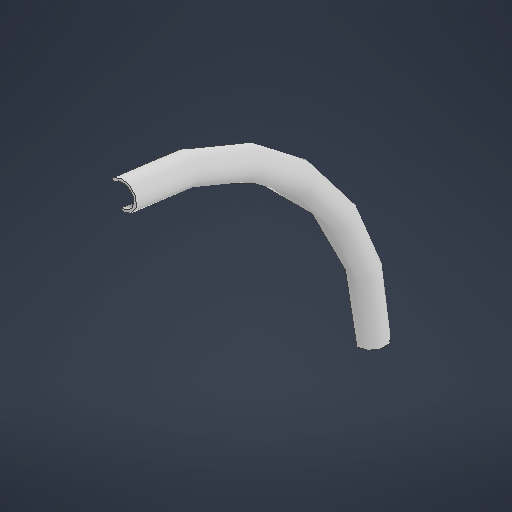
# Autodesk Inventor part: Track segment
Saved by Autodesk Inventor 2026.2 (Build 302298010, 298A)
## iProperties
Created: 2026-10-04
Part Number: Track segment
Material: Generisch
Document SubType Name: Modeling
Designer: denis
Mass: 20.068 g
Surface Area: 214.253 cm^2
Volume: 20.068 cm^3
Density: 1 g/cm^3
Appearance: Vorgabe
Author: denis
Autodesk Inventor part; units mm, degrees
ref_plane "YZ Plane" through (0, 0, 0) normal (1, 0, 0) x (0, 1, 0)
ref_plane "XZ Plane" through (0, 0, 0) normal (0, 1, 0) x (-1, 0, 0)
ref_plane "XY Plane" through (0, 0, 0) normal (0, 0, 1) x (1, 0, 0)
sketch "Skizze1" plane through (0, 0, 0) normal (0, 0, 1) x (1, 0, 0)
  line L0 (0, -37) -> (0, 222) construction
  line L1 (-61.25, 0) -> (61.25, 0) construction
  circle A0 centre (0, 175) radius 10
  line L2 (43.75, 0) -> (-43.75, 0)
  line L3 (0, 0) -> (0, 175) construction
  dimension "d0" = 20
  dimension "d1" = 175
  constraints: 4 end point, 1 centre point, 1 midpoint, 1 perpendicular, 1 point on line
  measures "d0" diameter of A0
  measures "d1" distance of L3.start L3.end
revolve "Umdrehung1" add sketch "Skizze1" angle 90 about axis through (43.75, 0, 0) along (-1, 0, 0)
sketch "Skizze3" plane through (0, 0, -175) normal (0, -1, 0) x (1, 0, 0)
  circle A0 centre (0, 0) radius 10 construction
  arc A1 (-6.222, -5.0286) -> (-0.8466, 7.9551) centre (0, 0) ccw
  line L0 (-6.4174, 12.6568) -> (-13.4859, -4.4167)
  line L1 (-13.4859, -4.4167) -> (-7.0686, -7.0736)
  line L2 (0, 10) -> (-6.4174, 12.6568)
  line L3 (-7.0686, -7.0736) -> (-6.222, -5.0286)
  line L4 (-0.8466, 7.9551) -> (0, 10)
  line L5 (-18.2735, 175) -> (15.2393, 175) projected
  point P0 (0, 175)
  dimension "d5" = 16
  constraints: 10 end point, 4 point on circle, 1 centre point, 1 coincident, 1 parallel, 1 perpendicular
  measures "d5" diameter of A1
revolve "Umdrehung3" cut sketch "Skizze3" angle 90 about axis through (-10, 0, 0) along (1, 0, 0)
